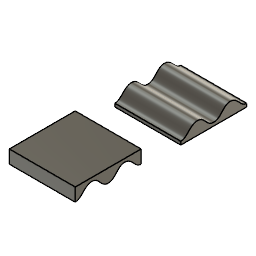
mould basic ridges v1 (Autodesk Fusion 360 design; units mm, degrees)
part number: 2026-06-01-15-53-17-386
Autodesk Fusion 360 part; units mm, degrees
sketch "Sketch1" plane through (0, 0, 0) normal (1, 0, 0) x (0, 1, 0)
sketch "Sketch2" plane through (0, 0, 0) normal (1, 0, 0) x (0, 1, 0)
sketch "Sketch3" plane through (0, 0, 0) normal (1, 0, 0) x (0, 1, 0)
  spline S0 degree 5 poles (0, 0) (1.1681, 0) (3.3824, 0.283) (6.3392, 1.5567) (9.7301, 4.6914) (13.9848, 9.565) (18.9749, 13.6486) (25.0863, 15.4307) (30.9185, 14.0277) (35.4014, 9.9901) (39.4836, 4.9316) (44.0979, 0.7791) (50.1025, -0.8037) (56.053, 0.8791) (60.6023, 5.0405) (64.6417, 10.101) (69.123, 14.2048) (74.9873, 15.7944) (81.0904, 14.1583) (86.0492, 10.0174) (90.266, 4.951) (93.64, 1.6466) (96.6, 0.2994) (98.8246, 0) (100, 0) knots 0 0 0 0 0 0 0.05 0.1 0.15 0.2 0.25 0.3 0.35 0.4 0.45 0.5 0.55 0.6 0.65 0.7 0.75 0.8 0.85 0.9 0.95 1 1 1 1 1 1
  line L0 (65, 15) -> (85, 15)
  line L1 (14.9102, 14.2886) -> (35, 15)
  line L2 (-10, 0) -> (10, 0)
  line L3 (90, 0) -> (110, 0)
  line L4 (0, -4.9999) -> (100, -4.9999)
  line L5 (100, -4.9999) -> (100, 0)
  line L6 (0, 0) -> (0, -4.9999)
  line L7 (40, 0) -> (60, 0)
  point P0 (24.9551, 14.6443)
  point P1 (50, 0)
  point P2 (75, 15)
  constraint coincident S0.start L6.start
  constraint midpoint P2 L0
  constraint midpoint P0 L1
  constraint midpoint S0.start L2
  constraint midpoint S0.end L3
  constraint parallel L2 L4
  constraint perpendicular L4 L6
  constraint midpoint P1 L7
extrude "Extrude1" add sketch "Sketch3" along normal blind 100 makes body 1
sketch "Sketch4" plane through (0, 0, 0) normal (1, 0, 0) x (0, 1, 0)
  line L0 (0, -5) -> (100, -5)
  line L1 (100, -5) -> (100, 55)
  line L2 (100, 55) -> (0, 55)
  line L3 (0, 55) -> (0, -5)
  constraint horizontal L0
  constraint vertical L1
  constraint horizontal L2
  constraint vertical L3
extrude "Extrude2" add sketch "Sketch4" against normal blind 100 separate body makes body 2
copy_body "CopyPasteBodies1" bodies 1 makes body 3
move_body "Move1" bodies 3 to x (1, 0, 0) y (0, 1, 0) z (0, 0, 1) at (0, 160, 0)
move_face "MoveFace1" by (100, 0, 5) 1 faces at (-33.3333, 66.6667, 55) on bodies 2
move_body "Move2" bodies 2 to x (1, 0, 0) y (0, 1, 0) z (0, 0, 1) at (100, 0, 5)
combine "Combine1" operation cut target body 2 tool bodies 1
extrude "Extrude3" cut 1 faces at (66.6667, 66.6667, 65) along direction (0, 0, -1) blind 40 on bodies 2 bodies 2
extrude "Extrude4" cut 1 faces at (66.6667, 66.6667, 25) along direction (0, 0, -1) blind 5 on bodies 2 bodies 2
